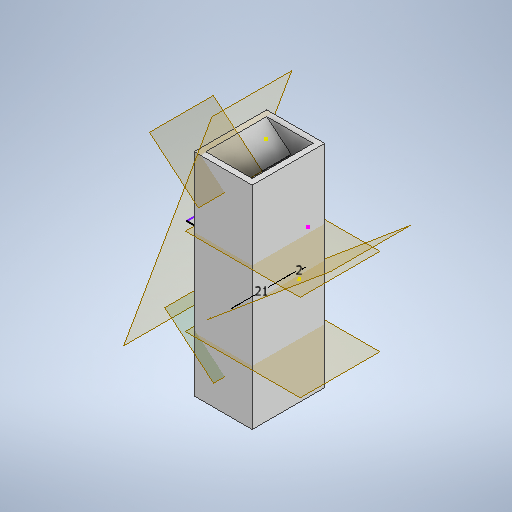
# Autodesk Inventor part: Semesterprojekt1magnetpakholder2
Saved by Autodesk Inventor 2027.1 (Build 311270010, 270A)
## iProperties
Created: 2026-10-22
Part Number: Semesterprojekt1magnetpakholder2
Material: Generic
Document SubType Name: Modeling
Designer: Sif Isaksen
Density: 1 g/cm^3
Appearance: Default
Author: Sif Isaksen
Autodesk Inventor part; units mm, degrees
ref_plane "YZ Plane" through (0, 0, 0) normal (1, 0, 0) x (0, 1, 0)
ref_plane "XZ Plane" through (0, 0, 0) normal (0, 1, 0) x (-1, 0, 0)
ref_plane "XY Plane" through (0, 0, 0) normal (0, 0, 1) x (1, 0, 0)
sketch "Sketch1" plane through (0, 0, 0) normal (0, 1, 0) x (-1, 0, 0)
  line L0 (8.8035, 16.1007) -> (-11.1965, 16.1007)
  line L1 (-11.1965, 16.1007) -> (-11.1965, -8.8993)
  line L2 (-11.1965, -8.8993) -> (8.8035, -8.8993)
  line L3 (8.8035, -8.8993) -> (8.8035, 16.1007)
  line L4 (6.8035, 14.1007) -> (-9.1965, 14.1007)
  line L5 (-9.1965, 14.1007) -> (-9.1965, -6.8993)
  line L6 (-9.1965, -6.8993) -> (6.8035, -6.8993)
  line L7 (6.8035, -6.8993) -> (6.8035, 14.1007)
  point P0 (0, 0)
  point P1 (8.8035, 3.6007)
  point P2 (6.8035, 3.6007)
  dimension "d0" = 20
  dimension "d1" = 25
  dimension "d2" = 16
  dimension "d3" = 21
  dimension "d4" = 2
  dimension "d5" = 2
  constraints: 16 end point, 4 parallel, 2 horizontal, 2 midpoint, 2 perpendicular
  measures "d0" distance of L2.end L1.end
  measures "d1" distance of L1.end L0.end
  measures "d2" distance of L6.end L5.end
  measures "d3" distance of L5.end L4.end
  measures "d4" distance of point (8.803, 3.601) point (6.803, 3.601)
  measures "d5" distance between parallel lines of L0 L4
extrude "Extrusion1" add sketch "Sketch1" along normal blind 36 and the other way blind 37
sketch "Sketch2" plane through (-6.8035, -37, 14.1007) normal (1, 0, 0) x (0, 0, -1)
  point P0 (14.1007, 37)
sketch "Sketch3" plane through (0, 36, 0) normal (0, 1, 0) x (1, 0, 0)
  point P0 (0, 0)
ref_plane "Work Plane8" through (-6.8035, 36, 14.1007) normal (0.6428, 0.766, 0) x (0, 0, 1)
sketch "Sketch5" plane through (-6.8035, 36, 14.1007) normal (0.6428, 0.766, 0) x (0, 0, 1)
  line L0 (0, 0) -> (-21, 0) projected
  line L1 (-21, 0) -> (0, 0)
  line L2 (0, 0) -> (0, 11)
  line L3 (0, 11) -> (-21, 11)
  line L4 (-21, 11) -> (-21, 0)
  point P0 (-14.1007, 28.3521)
  dimension "d13" = 21
  dimension "d14" = 11
  constraints: 8 end point, 2 parallel, 1 horizontal, 1 perpendicular
  measures "d13" distance of L3.end L2.end
  measures "d14" distance of L2.end L1.end
extrude "Extrusion3" add sketch "Sketch5" against normal blind 1
sketch "Sketch6" plane through (11.1965, -37, 16.1007) normal (1, 0, 0) x (0, 0, -1)
  point P0 (16.1007, 37)
sketch "Sketch7" plane through (0, 36, 0) normal (0, 1, 0) x (1, 0, 0)
  point P0 (0, 0)
sketch "Sketch8" plane through (-7.4463, 35.234, 14.1007) normal (-0.6428, -0.766, 0) x (-0.766, 0.6428, 0)
  point P0 (-28.3521, 14.1007)
sketch "Sketch11" plane through (9.1965, -37, -6.8993) normal (-1, 0, 0) x (0, 0, 1)
  point P0 (6.8993, 37)
sketch "Sketch15" plane through (0, 36, 0) normal (0, 1, 0) x (1, 0, 0)
  point P0 (0, 0)
ref_plane "Work Plane9" through (0, 12, 0) normal (0, 1, 0) x (1, 0, 0)
sketch "Sketch18" plane through (0, 12, 0) normal (0, 1, 0) x (1, 0, 0)
  line L0 (9.1965, 6.8993) -> (9.1965, -14.1007) projected
  line L1 (9.1965, 6.8993) -> (-6.8035, 6.8993) projected
  line L2 (9.1965, -14.1007) -> (-13.3749, -14.1007)
  line L3 (-13.3749, -14.1007) -> (-13.3749, 6.8993)
  line L4 (-13.3749, 6.8993) -> (9.1965, 6.8993)
  line L5 (9.1965, 6.8993) -> (9.1965, -14.1007)
  point P0 (0, 0)
  constraints: 8 end point, 2 parallel, 1 horizontal, 1 perpendicular, 1 point on line
ref_plane "Work Plane10" through (25.1965, 13, -1.6493) normal (-0.6428, 0.766, 0) x (0, 0, 1)
sketch "Sketch19" plane through (25.1965, 13, -1.6493) normal (-0.6428, 0.766, 0) x (0, 0, 1)
  line L0 (15.8817, -19.1589) -> (-5.1183, -19.1589)
  line L1 (-5.1183, -19.1589) -> (-5.1183, -28.1589)
  line L2 (-5.1183, -28.1589) -> (15.8817, -28.1589)
  line L3 (15.8817, -28.1589) -> (15.8817, -19.1589)
  point P0 (1.6493, -27.6579)
  dimension "d34" = 21
  dimension "d35" = 9
  constraints: 8 end point, 2 parallel, 1 horizontal, 1 perpendicular
  measures "d34" distance of L2.end L1.end
  measures "d35" distance of L1.end L0.end
extrude "Extrusion7" add sketch "Sketch19" against normal blind 1
sketch "Sketch20" plane through (0, -37, 0) normal (0, -1, 0) x (1, 0, 0)
  point P0 (0, 0)
ref_plane "Work Plane11" through (0, -18, 0) normal (0, 1, 0) x (1, 0, 0)
ref_plane "Work Plane13" through (-6.8035, -19, 8.8507) normal (-0.6428, -0.766, 0) x (0, 0, 1)
sketch "Sketch22" plane through (-6.8035, -19, 8.8507) normal (-0.6428, -0.766, 0) x (0, 0, 1)
  line L0 (-15.75, 0) -> (5.25, 0) projected
  line L1 (-15.75, 0) -> (5.25, 0)
  line L2 (5.25, 0) -> (5.25, -11)
  line L3 (5.25, -11) -> (-15.75, -11)
  line L4 (-15.75, -11) -> (-15.75, 0)
  point P0 (-8.8507, 7.0012)
  dimension "d46" = 21
  dimension "d47" = 11
  constraints: 8 end point, 2 parallel, 1 horizontal, 1 perpendicular
  measures "d46" distance of L2.end L3.end
  measures "d47" distance of L1.end L2.end
extrude "Extrusion9" add sketch "Sketch22" against normal blind 1
ref_plane "Work Plane14" through (-6.8035, 36, 14.1007) normal (0.9397, -0.342, 0) x (0, 0, -1)
sketch "Sketch24" plane through (11.1965, -37, -8.8993) normal (1, 0, 0) x (0, 0, -1)
  point P0 (-8.8993, 37)
sketch "Sketch25" plane through (25.1965, 13, -1.6493) normal (-0.6428, 0.766, 0) x (0, 0, 1)
  line L0 (15.75, -27.3945) -> (-5.25, -27.3945)
  line L1 (-5.25, -27.3945) -> (-5.25, -29.3945)
  line L2 (-5.25, -29.3945) -> (15.75, -29.3945)
  line L3 (15.75, -29.3945) -> (15.75, -27.3945)
  point P0 (1.6493, -27.6579)
  dimension "d54" = 21
  dimension "d55" = 2
  constraints: 8 end point, 2 parallel, 1 horizontal, 1 perpendicular
  measures "d54" distance of L2.end L1.end
  measures "d55" distance of L1.end L0.end
extrude "Extrusion11" cut sketch "Sketch25" against normal blind 1
extrude "Extrusion12" add sketch "Sketch25" against normal blind 1
body "Solid1"
